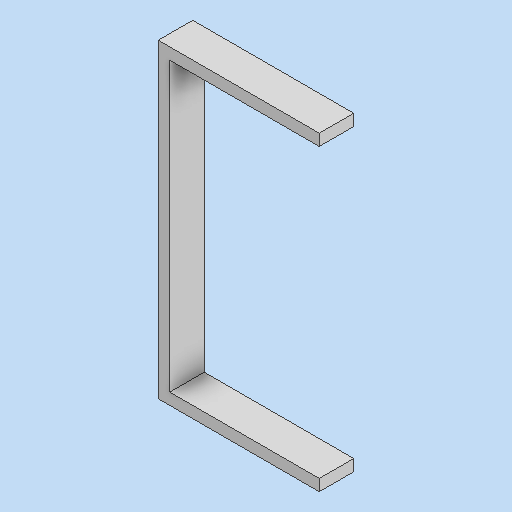
# Autodesk Inventor part: Stabi_version_2
Saved by Autodesk Inventor 2026 (Build 300175050, 175E)
## iProperties
Created: 2025-06-25
Part Number: Stabi_version_2
Material: Generisch
Document SubType Name: Modeling
Designer: karle
Density: 1 g/cm^3
Appearance: Vorgabe
Author: karle
Autodesk Inventor part; units mm, degrees
ref_plane "YZ Plane" through (0, 0, 0) normal (1, 0, 0) x (0, 1, 0)
ref_plane "XZ Plane" through (0, 0, 0) normal (0, 1, 0) x (-1, 0, 0)
ref_plane "XY Plane" through (0, 0, 0) normal (0, 0, 1) x (1, 0, 0)
sketch "Skizze1" plane through (0, 0, 0) normal (0, 0, 1) x (1, 0, 0)
  line L0 (0, 0) -> (-70, 0)
  line L1 (-70, 0) -> (-70, -135)
  line L2 (-70, -135) -> (0, -135)
  line L3 (0, -135) -> (0, -130)
  line L4 (0, -130) -> (-65, -130)
  line L5 (-65, -130) -> (-65, -5)
  line L6 (-65, -5) -> (0, -5)
  line L7 (0, -5) -> (0, 0)
  dimension "d0" = 5
  dimension "d1" = 5
  dimension "d2" = 5
  dimension "d3" = 125
  dimension "d4" = 65
  constraints: 16 end point, 7 perpendicular, 1 horizontal, 1 point on line
  measures "d0" distance between parallel lines of L6 L0
  measures "d1" distance between parallel lines of L1 L5
  measures "d2" distance between parallel lines of L2 L4
  measures "d3" distance between parallel lines of L4 L6
  measures "d4" distance between parallel lines of L7 L5
extrude "Extrusion1" add sketch "Skizze1" against normal blind 15
equation "\"d1\" = d0"
equation "\"d2\" = d0"
